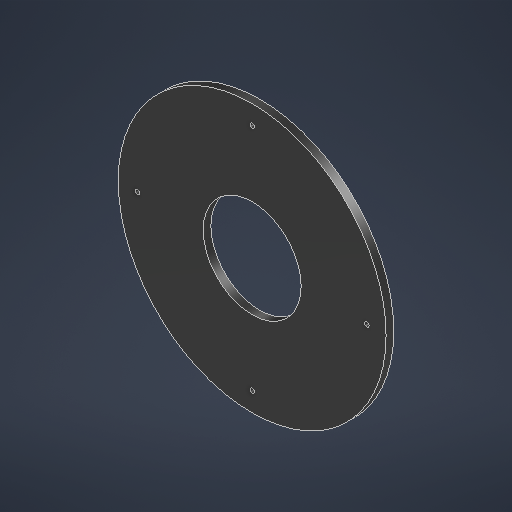
# Autodesk Inventor part: Part69
Saved by Autodesk Inventor 2027.1 (Build 311270010, 270A)
## iProperties
Created: 2026-10-12
Part Number: Part69
Material: Generic
Document SubType Name: Modeling
Designer: daniel
Density: 1 g/cm^3
Appearance: Glossy - Black
Mass: 104.038 g
Surface Area: 455.578 cm^2
Volume: 104.038 cm^3
Author: daniel
Autodesk Inventor part; units mm, degrees
ref_plane "YZ Plane" through (0, 0, 0) normal (1, 0, 0) x (0, 1, 0)
ref_plane "XZ Plane" through (0, 0, 0) normal (0, 1, 0) x (-1, 0, 0)
ref_plane "XY Plane" through (0, 0, 0) normal (0, 0, 1) x (1, 0, 0)
sketch "Sketch1" plane through (0, 0, 0) normal (0, 0, 1) x (1, 0, 0)
  circle A0 centre (7.5186, -0.377) radius 87.5
  circle A1 centre (7.5186, -0.377) radius 75
  circle A2 centre (82.5186, -0.377) radius 1.5
  circle A3 centre (7.5186, -75.377) radius 1.5
  circle A4 centre (7.5186, 74.623) radius 1.5
  circle A5 centre (-67.4814, -0.377) radius 1.5
  circle A6 centre (7.5186, -0.377) radius 32
  point P0 (0, 0)
  dimension "d4" = 175
  dimension "d5" = 150
  dimension "d7" = 3
  dimension "d8" = 3
  dimension "d9" = 3
  dimension "d10" = 3
  dimension "d13" = 64
  constraints: 7 centre point, 4 point on circle, 2 coincident
  measures "d4" diameter of A0
  measures "d5" diameter of A1
  measures "d7" diameter of A2
  measures "d8" diameter of A3
  measures "d9" diameter of A4
  measures "d10" diameter of A5
  measures "d13" diameter of A6
extrude "Extrusion1" add sketch "Sketch1" along normal blind 5 contours A0 | A2 A1 A3 A5 A4
equation "\"d4\" = 3.5 * d12"
equation "\"d8\" = d7"
equation "\"d9\" = d7"
equation "\"d10\" = d7"
equation "\"d12\" = 50"
body "Solid1"
